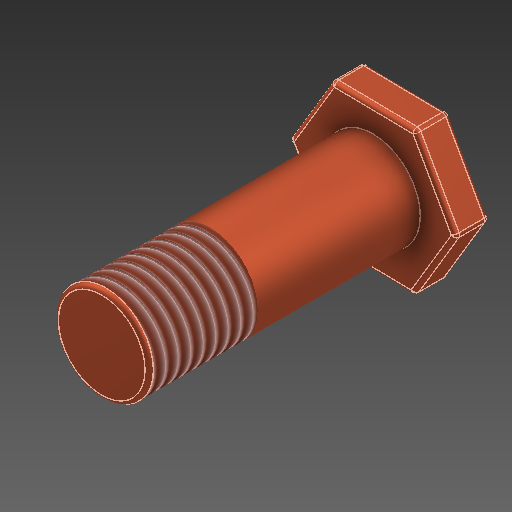
# Autodesk Inventor part: Perno Examen
Saved by Autodesk Inventor 2026.1 (Build 301233020, 233B)
## iProperties
Created: 2026-10-30
Part Number: Perno Examen
Material: Copper
Document SubType Name: Modeling
Designer: YmCris
Density: 8.94 g/cm^3
Appearance: Copper - Satin
Author: YmCris
Autodesk Inventor part; units mm, degrees
ref_plane "YZ Plane" through (0, 0, 0) normal (1, 0, 0) x (0, 1, 0)
ref_plane "XZ Plane" through (0, 0, 0) normal (0, 1, 0) x (-1, 0, 0)
ref_plane "XY Plane" through (0, 0, 0) normal (0, 0, 1) x (1, 0, 0)
sketch "Sketch1" plane through (0, 0, 0) normal (0, 0, 1) x (1, 0, 0)
  point P0 (0, 0)
sketch "Sketch2" plane through (0, 0, 0) normal (0, 0, 1) x (1, 0, 0)
  circle A0 centre (0, 0) radius 12.4
  dimension "d0" = 24.8
  constraints: 1 centre point, 1 coincident
  measures "d0" diameter of A0
extrude "Extrusion1" add sketch "Sketch2" along normal blind 9
sketch "Sketch4" plane through (0, 0, 9) normal (0, 0, 1) x (1, 0, 0)
  line L0 (0, 0) -> (19.5, 0)
  line L1 (0, 0) -> (-19.5, 0)
  line L2 (0, 0) -> (0, 17.32)
  line L3 (0, 0) -> (0, -17.32)
  line L4 (-9.75, 17.4607) -> (10.2464, 17.1741)
  line L5 (10.2464, 17.1741) -> (19.9964, -0.2866)
  line L6 (19.9964, -0.2866) -> (9.75, -17.4607)
  line L7 (9.75, -17.4607) -> (-10.2464, -17.1741)
  line L8 (-10.2464, -17.1741) -> (-19.9964, 0.2866)
  line L9 (-19.9964, 0.2866) -> (-9.75, 17.4607)
  dimension "d4" = 19.5
  dimension "d5" = 19.5
  dimension "d6" = 17.32
  dimension "d7" = 17.32
  constraints: 20 end point, 2 horizontal, 2 vertical, 1 coincident, 13 other
  measures "d4" distance of L0.start L0.end
  measures "d5" distance of L0.start L1.end
  measures "d6" distance of L0.start L2.end
  measures "d7" distance of L0.start L3.end
extrude "Extrusion2" add sketch "Sketch4" against normal blind 8
sketch "Sketch5" plane through (0, 0, 0) normal (0, 0, -1) x (-1, 0, 0)
  circle A0 centre (0, 0) radius 11.4
  dimension "d10" = 22.8
  constraints: 1 centre point, 1 coincident
  measures "d10" diameter of A0
extrude "Extrusion3" cut sketch "Sketch5" against normal blind 1
fillet "Fillet1" radius 1 18 edges at (-14.8732, 8.8736, 1) (0.2482, 17.3174, 1) (15.1214, 8.4437, 1) (14.8732, -8.8736, 1) (-0.2482, -17.3174, 1) (-15.1214, -8.4437, 1) (10.2464, 17.1741, 5) (15.1214, 8.4437, 9) (19.9964, -0.2866, 5) (0.2482, 17.3174, 9) (-9.75, 17.4607, 5) (-14.8732, 8.8736, 9) (-19.9964, 0.2866, 5) (-15.1214, -8.4437, 9) (-0.2482, -17.3174, 9) (-10.2464, -17.1741, 5) (9.75, -17.4607, 5) (14.8732, -8.8736, 9)
sketch "Sketch6" plane through (0, 0, 9) normal (0, 0, 1) x (1, 0, 0)
  circle A0 centre (0, 0) radius 11.4
  dimension "d14" = 22.8
  constraints: 1 centre point, 1 coincident
  measures "d14" diameter of A0
extrude "Extrusion4" add sketch "Sketch6" along normal blind 39
sketch "Sketch7" plane through (0, 0, 48) normal (0, 0, 1) x (1, 0, 0)
  circle A0 centre (0, 0) radius 11.4
  dimension "d17" = 22.8
  constraints: 1 centre point, 1 coincident
  measures "d17" diameter of A0
extrude "Extrusion5" add sketch "Sketch7" along normal blind 26
fillet "Fillet2" radius 1 1 edges at (-11.4, 0, 74)
thread "Thread1" size "M24x3" class "6g" standard "ANSI Metric M Profile" length 26 offset 39
body "Solid1"
